Autodesk Fusion 360 part; units mm, degrees
(part 2 of 5)
sketch "草图4" plane through (0, 0, 25.97) normal (0, 0, 1) x (1, 0, 0) in component "01_月饼_金_68mm"
  line L0 (12.6, 0) -> (12.5848, 0.6183)
  line L1 (12.5848, 0.6183) -> (12.5393, 1.235)
  line L2 (12.5393, 1.235) -> (12.4636, 1.8488)
  line L3 (12.4636, 1.8488) -> (12.3579, 2.4581)
  line L4 (12.3579, 2.4581) -> (12.2224, 3.0616)
  line L5 (12.2224, 3.0616) -> (12.0574, 3.6576)
  line L6 (12.0574, 3.6576) -> (11.8635, 4.2448)
  line L7 (11.8635, 4.2448) -> (11.6409, 4.8218)
  line L8 (11.6409, 4.8218) -> (11.3903, 5.3872)
  line L9 (11.3903, 5.3872) -> (11.1122, 5.9396)
  line L10 (11.1122, 5.9396) -> (10.8074, 6.4777)
  line L11 (10.8074, 6.4777) -> (10.4765, 7.0002)
  line L12 (10.4765, 7.0002) -> (10.1204, 7.5058)
  line L13 (10.1204, 7.5058) -> (9.7399, 7.9934)
  line L14 (9.7399, 7.9934) -> (9.336, 8.4616)
  line L15 (9.336, 8.4616) -> (8.9095, 8.9095)
  line L16 (8.9095, 8.9095) -> (8.4616, 9.336)
  line L17 (8.4616, 9.336) -> (7.9934, 9.7399)
  line L18 (7.9934, 9.7399) -> (7.5058, 10.1204)
  line L19 (7.5058, 10.1204) -> (7.0002, 10.4765)
  line L20 (7.0002, 10.4765) -> (6.4777, 10.8074)
  line L21 (6.4777, 10.8074) -> (5.9396, 11.1122)
  line L22 (5.9396, 11.1122) -> (5.3872, 11.3903)
  line L23 (5.3872, 11.3903) -> (4.8218, 11.6409)
  line L24 (4.8218, 11.6409) -> (4.2448, 11.8635)
  line L25 (4.2448, 11.8635) -> (3.6576, 12.0574)
  line L26 (3.6576, 12.0574) -> (3.0616, 12.2224)
  line L27 (3.0616, 12.2224) -> (2.4581, 12.3579)
  line L28 (2.4581, 12.3579) -> (1.8488, 12.4636)
  line L29 (1.8488, 12.4636) -> (1.235, 12.5393)
  line L30 (1.235, 12.5393) -> (0.6183, 12.5848)
  line L31 (0.6183, 12.5848) -> (0, 12.6)
  line L32 (0, 12.6) -> (-0.6183, 12.5848)
  line L33 (-0.6183, 12.5848) -> (-1.235, 12.5393)
  line L34 (-1.235, 12.5393) -> (-1.8488, 12.4636)
  line L35 (-1.8488, 12.4636) -> (-2.4581, 12.3579)
  line L36 (-2.4581, 12.3579) -> (-3.0616, 12.2224)
  line L37 (-3.0616, 12.2224) -> (-3.6576, 12.0574)
  line L38 (-3.6576, 12.0574) -> (-4.2448, 11.8635)
  line L39 (-4.2448, 11.8635) -> (-4.8218, 11.6409)
  line L40 (-4.8218, 11.6409) -> (-5.3872, 11.3903)
  line L41 (-5.3872, 11.3903) -> (-5.9396, 11.1122)
  line L42 (-5.9396, 11.1122) -> (-6.4777, 10.8074)
  line L43 (-6.4777, 10.8074) -> (-7.0002, 10.4765)
  line L44 (-7.0002, 10.4765) -> (-7.5058, 10.1204)
  line L45 (-7.5058, 10.1204) -> (-7.9934, 9.7399)
  line L46 (-7.9934, 9.7399) -> (-8.4616, 9.336)
  line L47 (-8.4616, 9.336) -> (-8.9095, 8.9095)
  line L48 (-8.9095, 8.9095) -> (-9.336, 8.4616)
  line L49 (-9.336, 8.4616) -> (-9.7399, 7.9934)
  line L50 (-9.7399, 7.9934) -> (-10.1204, 7.5058)
  line L51 (-10.1204, 7.5058) -> (-10.4765, 7.0002)
  line L52 (-10.4765, 7.0002) -> (-10.8074, 6.4777)
  line L53 (-10.8074, 6.4777) -> (-11.1122, 5.9396)
  line L54 (-11.1122, 5.9396) -> (-11.3903, 5.3872)
  line L55 (-11.3903, 5.3872) -> (-11.6409, 4.8218)
  line L56 (-11.6409, 4.8218) -> (-11.8635, 4.2448)
  line L57 (-11.8635, 4.2448) -> (-12.0574, 3.6576)
  line L58 (-12.0574, 3.6576) -> (-12.2224, 3.0616)
  line L59 (-12.2224, 3.0616) -> (-12.3579, 2.4581)
  line L60 (-12.3579, 2.4581) -> (-12.4636, 1.8488)
  line L61 (-12.4636, 1.8488) -> (-12.5393, 1.235)
  line L62 (-12.5393, 1.235) -> (-12.5848, 0.6183)
  line L63 (-12.5848, 0.6183) -> (-12.6, 0)
  line L64 (-12.6, 0) -> (-12.5848, -0.6183)
  line L65 (-12.5848, -0.6183) -> (-12.5393, -1.235)
  line L66 (-12.5393, -1.235) -> (-12.4636, -1.8488)
  line L67 (-12.4636, -1.8488) -> (-12.3579, -2.4581)
  line L68 (-12.3579, -2.4581) -> (-12.2224, -3.0616)
  line L69 (-12.2224, -3.0616) -> (-12.0574, -3.6576)
  line L70 (-12.0574, -3.6576) -> (-11.8635, -4.2448)
  line L71 (-11.8635, -4.2448) -> (-11.6409, -4.8218)
  line L72 (-11.6409, -4.8218) -> (-11.3903, -5.3872)
  line L73 (-11.3903, -5.3872) -> (-11.1122, -5.9396)
  line L74 (-11.1122, -5.9396) -> (-10.8074, -6.4777)
  line L75 (-10.8074, -6.4777) -> (-10.4765, -7.0002)
  line L76 (-10.4765, -7.0002) -> (-10.1204, -7.5058)
  line L77 (-10.1204, -7.5058) -> (-9.7399, -7.9934)
  line L78 (-9.7399, -7.9934) -> (-9.336, -8.4616)
  line L79 (-9.336, -8.4616) -> (-8.9095, -8.9095)
  line L80 (-8.9095, -8.9095) -> (-8.4616, -9.336)
  line L81 (-8.4616, -9.336) -> (-7.9934, -9.7399)
  line L82 (-7.9934, -9.7399) -> (-7.5058, -10.1204)
  line L83 (-7.5058, -10.1204) -> (-7.0002, -10.4765)
  line L84 (-7.0002, -10.4765) -> (-6.4777, -10.8074)
  line L85 (-6.4777, -10.8074) -> (-5.9396, -11.1122)
  line L86 (-5.9396, -11.1122) -> (-5.3872, -11.3903)
  line L87 (-5.3872, -11.3903) -> (-4.8218, -11.6409)
  line L88 (-4.8218, -11.6409) -> (-4.2448, -11.8635)
  line L89 (-4.2448, -11.8635) -> (-3.6576, -12.0574)
  line L90 (-3.6576, -12.0574) -> (-3.0616, -12.2224)
  line L91 (-3.0616, -12.2224) -> (-2.4581, -12.3579)
  line L92 (-2.4581, -12.3579) -> (-1.8488, -12.4636)
  line L93 (-1.8488, -12.4636) -> (-1.235, -12.5393)
  line L94 (-1.235, -12.5393) -> (-0.6183, -12.5848)
  line L95 (-0.6183, -12.5848) -> (0, -12.6)
  line L96 (0, -12.6) -> (0.6183, -12.5848)
  line L97 (0.6183, -12.5848) -> (1.235, -12.5393)
  line L98 (1.235, -12.5393) -> (1.8488, -12.4636)
  line L99 (1.8488, -12.4636) -> (2.4581, -12.3579)
  line L100 (2.4581, -12.3579) -> (3.0616, -12.2224)
  line L101 (3.0616, -12.2224) -> (3.6576, -12.0574)
  line L102 (3.6576, -12.0574) -> (4.2448, -11.8635)
  line L103 (4.2448, -11.8635) -> (4.8218, -11.6409)
  line L104 (4.8218, -11.6409) -> (5.3872, -11.3903)
  line L105 (5.3872, -11.3903) -> (5.9396, -11.1122)
  line L106 (5.9396, -11.1122) -> (6.4777, -10.8074)
  line L107 (6.4777, -10.8074) -> (7.0002, -10.4765)
  line L108 (7.0002, -10.4765) -> (7.5058, -10.1204)
  line L109 (7.5058, -10.1204) -> (7.9934, -9.7399)
  line L110 (7.9934, -9.7399) -> (8.4616, -9.336)
  line L111 (8.4616, -9.336) -> (8.9095, -8.9095)
  line L112 (8.9095, -8.9095) -> (9.336, -8.4616)
  line L113 (9.336, -8.4616) -> (9.7399, -7.9934)
  line L114 (9.7399, -7.9934) -> (10.1204, -7.5058)
  line L115 (10.1204, -7.5058) -> (10.4765, -7.0002)
  line L116 (10.4765, -7.0002) -> (10.8074, -6.4777)
  line L117 (10.8074, -6.4777) -> (11.1122, -5.9396)
  line L118 (11.1122, -5.9396) -> (11.3903, -5.3872)
  line L119 (11.3903, -5.3872) -> (11.6409, -4.8218)
  line L120 (11.6409, -4.8218) -> (11.8635, -4.2448)
  line L121 (11.8635, -4.2448) -> (12.0574, -3.6576)
  line L122 (12.0574, -3.6576) -> (12.2224, -3.0616)
  line L123 (12.2224, -3.0616) -> (12.3579, -2.4581)
  line L124 (12.3579, -2.4581) -> (12.4636, -1.8488)
  line L125 (12.4636, -1.8488) -> (12.5393, -1.235)
  line L126 (12.5393, -1.235) -> (12.5848, -0.6183)
  line L127 (12.5848, -0.6183) -> (12.6, 0)
  line L128 (11.7858, -0.579) -> (11.7432, -1.1566)
  line L129 (11.7432, -1.1566) -> (11.6723, -1.7314)
  line L130 (11.6723, -1.7314) -> (11.5733, -2.3021)
  line L131 (11.5733, -2.3021) -> (11.4464, -2.8672)
  line L132 (11.4464, -2.8672) -> (11.2919, -3.4254)
  line L133 (11.2919, -3.4254) -> (11.1102, -3.9753)
  line L134 (11.1102, -3.9753) -> (10.9018, -4.5157)
  line L135 (10.9018, -4.5157) -> (10.6671, -5.0452)
  line L136 (10.6671, -5.0452) -> (10.4067, -5.5625)
  line L137 (10.4067, -5.5625) -> (10.1212, -6.0664)
  line L138 (10.1212, -6.0664) -> (9.8113, -6.5557)
  line L139 (9.8113, -6.5557) -> (9.4778, -7.0293)
  line L140 (9.4778, -7.0293) -> (9.1215, -7.4858)
  line L141 (9.1215, -7.4858) -> (8.7432, -7.9244)
  line L142 (8.7432, -7.9244) -> (8.3439, -8.3439)
  line L143 (8.3439, -8.3439) -> (7.9244, -8.7432)
  line L144 (7.9244, -8.7432) -> (7.4858, -9.1215)
  line L145 (7.4858, -9.1215) -> (7.0293, -9.4778)
  line L146 (7.0293, -9.4778) -> (6.5557, -9.8113)
  line L147 (6.5557, -9.8113) -> (6.0664, -10.1212)
  line L148 (6.0664, -10.1212) -> (5.5625, -10.4067)
  line L149 (5.5625, -10.4067) -> (5.0452, -10.6671)
  line L150 (5.0452, -10.6671) -> (4.5157, -10.9018)
  line L151 (4.5157, -10.9018) -> (3.9753, -11.1102)
  line L152 (3.9753, -11.1102) -> (3.4254, -11.2919)
  line L153 (3.4254, -11.2919) -> (2.8672, -11.4464)
  line L154 (2.8672, -11.4464) -> (2.3021, -11.5733)
  line L155 (2.3021, -11.5733) -> (1.7314, -11.6723)
  line L156 (1.7314, -11.6723) -> (1.1566, -11.7432)
  line L157 (1.1566, -11.7432) -> (0.579, -11.7858)
  line L158 (0.579, -11.7858) -> (0, -11.8)
  line L159 (0, -11.8) -> (-0.579, -11.7858)
  line L160 (-0.579, -11.7858) -> (-1.1566, -11.7432)
  line L161 (-1.1566, -11.7432) -> (-1.7314, -11.6723)
  line L162 (-1.7314, -11.6723) -> (-2.3021, -11.5733)
  line L163 (-2.3021, -11.5733) -> (-2.8672, -11.4464)
  line L164 (-2.8672, -11.4464) -> (-3.4254, -11.2919)
  line L165 (-3.4254, -11.2919) -> (-3.9753, -11.1102)
  line L166 (-3.9753, -11.1102) -> (-4.5157, -10.9018)
  line L167 (-4.5157, -10.9018) -> (-5.0452, -10.6671)
  line L168 (-5.0452, -10.6671) -> (-5.5625, -10.4067)
  line L169 (-5.5625, -10.4067) -> (-6.0664, -10.1212)
  line L170 (-6.0664, -10.1212) -> (-6.5557, -9.8113)
  line L171 (-6.5557, -9.8113) -> (-7.0293, -9.4778)
  line L172 (-7.0293, -9.4778) -> (-7.4858, -9.1215)
  line L173 (-7.4858, -9.1215) -> (-7.9244, -8.7432)
  line L174 (-7.9244, -8.7432) -> (-8.3439, -8.3439)
  line L175 (-8.3439, -8.3439) -> (-8.7432, -7.9244)
  line L176 (-8.7432, -7.9244) -> (-9.1215, -7.4858)
  line L177 (-9.1215, -7.4858) -> (-9.4778, -7.0293)
  line L178 (-9.4778, -7.0293) -> (-9.8113, -6.5557)
  line L179 (-9.8113, -6.5557) -> (-10.1212, -6.0664)
  line L180 (-10.1212, -6.0664) -> (-10.4067, -5.5625)
  line L181 (-10.4067, -5.5625) -> (-10.6671, -5.0452)
  line L182 (-10.6671, -5.0452) -> (-10.9018, -4.5157)
  line L183 (-10.9018, -4.5157) -> (-11.1102, -3.9753)
  line L184 (-11.1102, -3.9753) -> (-11.2919, -3.4254)
  line L185 (-11.2919, -3.4254) -> (-11.4464, -2.8672)
  line L186 (-11.4464, -2.8672) -> (-11.5733, -2.3021)
  line L187 (-11.5733, -2.3021) -> (-11.6723, -1.7314)
  line L188 (-11.6723, -1.7314) -> (-11.7432, -1.1566)
  line L189 (-11.7432, -1.1566) -> (-11.7858, -0.579)
  line L190 (-11.7858, -0.579) -> (-11.8, 0)
  line L191 (-11.8, 0) -> (-11.7858, 0.579)
  line L192 (-11.7858, 0.579) -> (-11.7432, 1.1566)
  line L193 (-11.7432, 1.1566) -> (-11.6723, 1.7314)
  line L194 (-11.6723, 1.7314) -> (-11.5733, 2.3021)
  line L195 (-11.5733, 2.3021) -> (-11.4464, 2.8672)
  line L196 (-11.4464, 2.8672) -> (-11.2919, 3.4254)
  line L197 (-11.2919, 3.4254) -> (-11.1102, 3.9753)
  line L198 (-11.1102, 3.9753) -> (-10.9018, 4.5157)
  line L199 (-10.9018, 4.5157) -> (-10.6671, 5.0452)
  line L200 (-10.6671, 5.0452) -> (-10.4067, 5.5625)
  line L201 (-10.4067, 5.5625) -> (-10.1212, 6.0664)
  line L202 (-10.1212, 6.0664) -> (-9.8113, 6.5557)
  line L203 (-9.8113, 6.5557) -> (-9.4778, 7.0293)
  line L204 (-9.4778, 7.0293) -> (-9.1215, 7.4858)
  line L205 (-9.1215, 7.4858) -> (-8.7432, 7.9244)
  line L206 (-8.7432, 7.9244) -> (-8.3439, 8.3439)
  line L207 (-8.3439, 8.3439) -> (-7.9244, 8.7432)
  line L208 (-7.9244, 8.7432) -> (-7.4858, 9.1215)
  line L209 (-7.4858, 9.1215) -> (-7.0293, 9.4778)
  line L210 (-7.0293, 9.4778) -> (-6.5557, 9.8113)
  line L211 (-6.5557, 9.8113) -> (-6.0664, 10.1212)
  line L212 (-6.0664, 10.1212) -> (-5.5625, 10.4067)
  line L213 (-5.5625, 10.4067) -> (-5.0452, 10.6671)
  line L214 (-5.0452, 10.6671) -> (-4.5157, 10.9018)
  line L215 (-4.5157, 10.9018) -> (-3.9753, 11.1102)
  line L216 (-3.9753, 11.1102) -> (-3.4254, 11.2919)
  line L217 (-3.4254, 11.2919) -> (-2.8672, 11.4464)
  line L218 (-2.8672, 11.4464) -> (-2.3021, 11.5733)
  line L219 (-2.3021, 11.5733) -> (-1.7314, 11.6723)
  line L220 (-1.7314, 11.6723) -> (-1.1566, 11.7432)
  line L221 (-1.1566, 11.7432) -> (-0.579, 11.7858)
  line L222 (-0.579, 11.7858) -> (0, 11.8)
  line L223 (0, 11.8) -> (0.579, 11.7858)
  line L224 (0.579, 11.7858) -> (1.1566, 11.7432)
  line L225 (1.1566, 11.7432) -> (1.7314, 11.6723)
  line L226 (1.7314, 11.6723) -> (2.3021, 11.5733)
  line L227 (2.3021, 11.5733) -> (2.8672, 11.4464)
  line L228 (2.8672, 11.4464) -> (3.4254, 11.2919)
  line L229 (3.4254, 11.2919) -> (3.9753, 11.1102)
  line L230 (3.9753, 11.1102) -> (4.5157, 10.9018)
  line L231 (4.5157, 10.9018) -> (5.0452, 10.6671)
  line L232 (5.0452, 10.6671) -> (5.5625, 10.4067)
  line L233 (5.5625, 10.4067) -> (6.0664, 10.1212)
  line L234 (6.0664, 10.1212) -> (6.5557, 9.8113)
  line L235 (6.5557, 9.8113) -> (7.0293, 9.4778)
  line L236 (7.0293, 9.4778) -> (7.4858, 9.1215)
  line L237 (7.4858, 9.1215) -> (7.9244, 8.7432)
  line L238 (7.9244, 8.7432) -> (8.3439, 8.3439)
  line L239 (8.3439, 8.3439) -> (8.7432, 7.9244)
  line L240 (8.7432, 7.9244) -> (9.1215, 7.4858)
  line L241 (9.1215, 7.4858) -> (9.4778, 7.0293)
  line L242 (9.4778, 7.0293) -> (9.8113, 6.5557)
  line L243 (9.8113, 6.5557) -> (10.1212, 6.0664)
  line L244 (10.1212, 6.0664) -> (10.4067, 5.5625)
  line L245 (10.4067, 5.5625) -> (10.6671, 5.0452)
  line L246 (10.6671, 5.0452) -> (10.9018, 4.5157)
  line L247 (10.9018, 4.5157) -> (11.1102, 3.9753)
  line L248 (11.1102, 3.9753) -> (11.2919, 3.4254)
  line L249 (11.2919, 3.4254) -> (11.4464, 2.8672)
  line L250 (11.4464, 2.8672) -> (11.5733, 2.3021)
  line L251 (11.5733, 2.3021) -> (11.6723, 1.7314)
  line L252 (11.6723, 1.7314) -> (11.7432, 1.1566)
  line L253 (11.7432, 1.1566) -> (11.7858, 0.579)
  line L254 (11.7858, 0.579) -> (11.8, 0)
  line L255 (11.8, 0) -> (11.7858, -0.579)
extrude "团圆内环_003 (1)" add sketch "草图4" along normal blind 1.63 bodies 1 in component "01_月饼_金_68mm"
sketch "草图5" plane through (0, 0, 25.97) normal (0, 0, 1) x (1, 0, 0) in component "01_月饼_金_68mm"
  line L0 (23.66, 0) -> (23.5783, 0.5788)
  line L1 (23.5783, 0.5788) -> (23.3448, 1.1469)
  line L2 (23.3448, 1.1469) -> (22.9926, 1.696)
  line L3 (22.9926, 1.696) -> (22.5708, 2.223)
  line L4 (22.5708, 2.223) -> (22.1372, 2.7304)
  line L5 (22.1372, 2.7304) -> (21.7491, 3.2262)
  line L6 (21.7491, 3.2262) -> (21.454, 3.7226)
  line L7 (21.454, 3.7226) -> (21.283, 4.2335)
  line L8 (21.283, 4.2335) -> (21.2455, 4.7708)
  line L9 (21.2455, 4.7708) -> (21.3281, 5.3424)
  line L10 (21.3281, 5.3424) -> (21.497, 5.949)
  line L11 (21.497, 5.949) -> (21.7034, 6.5837)
  line L12 (21.7034, 6.5837) -> (21.8914, 7.2319)
  line L13 (21.8914, 7.2319) -> (22.0067, 7.8741)
  line L14 (22.0067, 7.8741) -> (22.005, 8.4883)
  line L15 (22.005, 8.4883) -> (21.859, 9.0543)
  line L16 (21.859, 9.0543) -> (21.562, 9.5578)
  line L17 (21.562, 9.5578) -> (21.1289, 9.9932)
  line L18 (21.1289, 9.9932) -> (20.5933, 10.3658)
  line L19 (20.5933, 10.3658) -> (20.002, 10.6913)
  line L20 (20.002, 10.6913) -> (19.4073, 10.9941)
  line L21 (19.4073, 10.9941) -> (18.8589, 11.3036)
  line L22 (18.8589, 11.3036) -> (18.3963, 11.6494)
  line L23 (18.3963, 11.6494) -> (18.0429, 12.0559)
  line L24 (18.0429, 12.0559) -> (17.8026, 12.538)
  line L25 (17.8026, 12.538) -> (17.6602, 13.0977)
  line L26 (17.6602, 13.0977) -> (17.584, 13.7227)
  line L27 (17.584, 13.7227) -> (17.5319, 14.388)
  line L28 (17.5319, 14.388) -> (17.4575, 15.0589)
  line L29 (17.4575, 15.0589) -> (17.3182, 15.6963)
  line L30 (17.3182, 15.6963) -> (17.0817, 16.2631)
  line L31 (17.0817, 16.2631) -> (16.7301, 16.7301)
  line L32 (16.7301, 16.7301) -> (16.2631, 17.0817)
  line L33 (16.2631, 17.0817) -> (15.6963, 17.3182)
  line L34 (15.6963, 17.3182) -> (15.0589, 17.4575)
  line L35 (15.0589, 17.4575) -> (14.388, 17.5319)
  line L36 (14.388, 17.5319) -> (13.7227, 17.584)
  line L37 (13.7227, 17.584) -> (13.0977, 17.6602)
  line L38 (13.0977, 17.6602) -> (12.538, 17.8026)
  line L39 (12.538, 17.8026) -> (12.0559, 18.0429)
  line L40 (12.0559, 18.0429) -> (11.6494, 18.3963)
  line L41 (11.6494, 18.3963) -> (11.3036, 18.8589)
  line L42 (11.3036, 18.8589) -> (10.9941, 19.4073)
  line L43 (10.9941, 19.4073) -> (10.6913, 20.002)
  line L44 (10.6913, 20.002) -> (10.3658, 20.5933)
  line L45 (10.3658, 20.5933) -> (9.9932, 21.1289)
  line L46 (9.9932, 21.1289) -> (9.5578, 21.562)
  line L47 (9.5578, 21.562) -> (9.0543, 21.859)
  line L48 (9.0543, 21.859) -> (8.4883, 22.005)
  line L49 (8.4883, 22.005) -> (7.8741, 22.0067)
  line L50 (7.8741, 22.0067) -> (7.2319, 21.8914)
  line L51 (7.2319, 21.8914) -> (6.5837, 21.7034)
  line L52 (6.5837, 21.7034) -> (5.949, 21.497)
  line L53 (5.949, 21.497) -> (5.3424, 21.3281)
  line L54 (5.3424, 21.3281) -> (4.7708, 21.2455)
  line L55 (4.7708, 21.2455) -> (4.2335, 21.283)
  line L56 (4.2335, 21.283) -> (3.7226, 21.454)
  line L57 (3.7226, 21.454) -> (3.2262, 21.7491)
  line L58 (3.2262, 21.7491) -> (2.7304, 22.1372)
  line L59 (2.7304, 22.1372) -> (2.223, 22.5708)
  line L60 (2.223, 22.5708) -> (1.696, 22.9926)
  line L61 (1.696, 22.9926) -> (1.1469, 23.3448)
  line L62 (1.1469, 23.3448) -> (0.5788, 23.5783)
  line L63 (0.5788, 23.5783) -> (0, 23.66)
  line L64 (0, 23.66) -> (-0.5788, 23.5783)
  line L65 (-0.5788, 23.5783) -> (-1.1469, 23.3448)
  line L66 (-1.1469, 23.3448) -> (-1.696, 22.9926)
  line L67 (-1.696, 22.9926) -> (-2.223, 22.5708)
  line L68 (-2.223, 22.5708) -> (-2.7304, 22.1372)
  line L69 (-2.7304, 22.1372) -> (-3.2262, 21.7491)
  line L70 (-3.2262, 21.7491) -> (-3.7226, 21.454)
  line L71 (-3.7226, 21.454) -> (-4.2335, 21.283)
  line L72 (-4.2335, 21.283) -> (-4.7708, 21.2455)
  line L73 (-4.7708, 21.2455) -> (-5.3424, 21.3281)
  line L74 (-5.3424, 21.3281) -> (-5.949, 21.497)
  line L75 (-5.949, 21.497) -> (-6.5837, 21.7034)
  line L76 (-6.5837, 21.7034) -> (-7.2319, 21.8914)
  line L77 (-7.2319, 21.8914) -> (-7.8741, 22.0067)
  line L78 (-7.8741, 22.0067) -> (-8.4883, 22.005)
  line L79 (-8.4883, 22.005) -> (-9.0543, 21.859)
  line L80 (-9.0543, 21.859) -> (-9.5578, 21.562)
  line L81 (-9.5578, 21.562) -> (-9.9932, 21.1289)
  line L82 (-9.9932, 21.1289) -> (-10.3658, 20.5933)
  line L83 (-10.3658, 20.5933) -> (-10.6913, 20.002)
  line L84 (-10.6913, 20.002) -> (-10.9941, 19.4073)
  line L85 (-10.9941, 19.4073) -> (-11.3036, 18.8589)
  line L86 (-11.3036, 18.8589) -> (-11.6494, 18.3963)
  line L87 (-11.6494, 18.3963) -> (-12.0559, 18.0429)
  line L88 (-12.0559, 18.0429) -> (-12.538, 17.8026)
  line L89 (-12.538, 17.8026) -> (-13.0977, 17.6602)
  line L90 (-13.0977, 17.6602) -> (-13.7227, 17.584)
  line L91 (-13.7227, 17.584) -> (-14.388, 17.5319)
  line L92 (-14.388, 17.5319) -> (-15.0589, 17.4575)
  line L93 (-15.0589, 17.4575) -> (-15.6963, 17.3182)
  line L94 (-15.6963, 17.3182) -> (-16.2631, 17.0817)
  line L95 (-16.2631, 17.0817) -> (-16.7301, 16.7301)
  line L96 (-16.7301, 16.7301) -> (-17.0817, 16.2631)
  line L97 (-17.0817, 16.2631) -> (-17.3182, 15.6963)
  line L98 (-17.3182, 15.6963) -> (-17.4575, 15.0589)
  line L99 (-17.4575, 15.0589) -> (-17.5319, 14.388)
  line L100 (-17.5319, 14.388) -> (-17.584, 13.7227)
  line L101 (-17.584, 13.7227) -> (-17.6602, 13.0977)
  line L102 (-17.6602, 13.0977) -> (-17.8026, 12.538)
  line L103 (-17.8026, 12.538) -> (-18.0429, 12.0559)
  line L104 (-18.0429, 12.0559) -> (-18.3963, 11.6494)
  line L105 (-18.3963, 11.6494) -> (-18.8589, 11.3036)
  line L106 (-18.8589, 11.3036) -> (-19.4073, 10.9941)
  line L107 (-19.4073, 10.9941) -> (-20.002, 10.6913)
  line L108 (-20.002, 10.6913) -> (-20.5933, 10.3658)
  line L109 (-20.5933, 10.3658) -> (-21.1289, 9.9932)
  line L110 (-21.1289, 9.9932) -> (-21.562, 9.5578)
  line L111 (-21.562, 9.5578) -> (-21.859, 9.0543)
  line L112 (-21.859, 9.0543) -> (-22.005, 8.4883)
  line L113 (-22.005, 8.4883) -> (-22.0067, 7.8741)
  line L114 (-22.0067, 7.8741) -> (-21.8914, 7.2319)
  line L115 (-21.8914, 7.2319) -> (-21.7034, 6.5837)
  line L116 (-21.7034, 6.5837) -> (-21.497, 5.949)
  line L117 (-21.497, 5.949) -> (-21.3281, 5.3424)
  line L118 (-21.3281, 5.3424) -> (-21.2455, 4.7708)
  line L119 (-21.2455, 4.7708) -> (-21.283, 4.2335)
  line L120 (-21.283, 4.2335) -> (-21.454, 3.7226)
  line L121 (-21.454, 3.7226) -> (-21.7491, 3.2262)
  line L122 (-21.7491, 3.2262) -> (-22.1372, 2.7304)
  line L123 (-22.1372, 2.7304) -> (-22.5708, 2.223)
  line L124 (-22.5708, 2.223) -> (-22.9926, 1.696)
  line L125 (-22.9926, 1.696) -> (-23.3448, 1.1469)
  line L126 (-23.3448, 1.1469) -> (-23.5783, 0.5788)
  line L127 (-23.5783, 0.5788) -> (-23.66, 0)
  line L128 (-23.66, 0) -> (-23.5783, -0.5788)
  line L129 (-23.5783, -0.5788) -> (-23.3448, -1.1469)
  line L130 (-23.3448, -1.1469) -> (-22.9926, -1.696)
  line L131 (-22.9926, -1.696) -> (-22.5708, -2.223)
  line L132 (-22.5708, -2.223) -> (-22.1372, -2.7304)
  line L133 (-22.1372, -2.7304) -> (-21.7491, -3.2262)
  line L134 (-21.7491, -3.2262) -> (-21.454, -3.7226)
  line L135 (-21.454, -3.7226) -> (-21.283, -4.2335)
  line L136 (-21.283, -4.2335) -> (-21.2455, -4.7708)
  line L137 (-21.2455, -4.7708) -> (-21.3281, -5.3424)
  line L138 (-21.3281, -5.3424) -> (-21.497, -5.949)
  line L139 (-21.497, -5.949) -> (-21.7034, -6.5837)
  line L140 (-21.7034, -6.5837) -> (-21.8914, -7.2319)
  line L141 (-21.8914, -7.2319) -> (-22.0067, -7.8741)
  line L142 (-22.0067, -7.8741) -> (-22.005, -8.4883)
  line L143 (-22.005, -8.4883) -> (-21.859, -9.0543)
  line L144 (-21.859, -9.0543) -> (-21.562, -9.5578)
  line L145 (-21.562, -9.5578) -> (-21.1289, -9.9932)
  line L146 (-21.1289, -9.9932) -> (-20.5933, -10.3658)
  line L147 (-20.5933, -10.3658) -> (-20.002, -10.6913)
  line L148 (-20.002, -10.6913) -> (-19.4073, -10.9941)
  line L149 (-19.4073, -10.9941) -> (-18.8589, -11.3036)
  line L150 (-18.8589, -11.3036) -> (-18.3963, -11.6494)
  line L151 (-18.3963, -11.6494) -> (-18.0429, -12.0559)
  line L152 (-18.0429, -12.0559) -> (-17.8026, -12.538)
  line L153 (-17.8026, -12.538) -> (-17.6602, -13.0977)
  line L154 (-17.6602, -13.0977) -> (-17.584, -13.7227)
  line L155 (-17.584, -13.7227) -> (-17.5319, -14.388)
  line L156 (-17.5319, -14.388) -> (-17.4575, -15.0589)
  line L157 (-17.4575, -15.0589) -> (-17.3182, -15.6963)
  line L158 (-17.3182, -15.6963) -> (-17.0817, -16.2631)
  line L159 (-17.0817, -16.2631) -> (-16.7301, -16.7301)
  line L160 (-16.7301, -16.7301) -> (-16.2631, -17.0817)
  line L161 (-16.2631, -17.0817) -> (-15.6963, -17.3182)
  line L162 (-15.6963, -17.3182) -> (-15.0589, -17.4575)
  line L163 (-15.0589, -17.4575) -> (-14.388, -17.5319)
  line L164 (-14.388, -17.5319) -> (-13.7227, -17.584)
  line L165 (-13.7227, -17.584) -> (-13.0977, -17.6602)
  line L166 (-13.0977, -17.6602) -> (-12.538, -17.8026)
  line L167 (-12.538, -17.8026) -> (-12.0559, -18.0429)
  line L168 (-12.0559, -18.0429) -> (-11.6494, -18.3963)
  line L169 (-11.6494, -18.3963) -> (-11.3036, -18.8589)
  line L170 (-11.3036, -18.8589) -> (-10.9941, -19.4073)
  line L171 (-10.9941, -19.4073) -> (-10.6913, -20.002)
  line L172 (-10.6913, -20.002) -> (-10.3658, -20.5933)
  line L173 (-10.3658, -20.5933) -> (-9.9932, -21.1289)
  line L174 (-9.9932, -21.1289) -> (-9.5578, -21.562)
  line L175 (-9.5578, -21.562) -> (-9.0543, -21.859)
  line L176 (-9.0543, -21.859) -> (-8.4883, -22.005)
  line L177 (-8.4883, -22.005) -> (-7.8741, -22.0067)
  line L178 (-7.8741, -22.0067) -> (-7.2319, -21.8914)
  line L179 (-7.2319, -21.8914) -> (-6.5837, -21.7034)
  line L180 (-6.5837, -21.7034) -> (-5.949, -21.497)
  line L181 (-5.949, -21.497) -> (-5.3424, -21.3281)
  line L182 (-5.3424, -21.3281) -> (-4.7708, -21.2455)
  line L183 (-4.7708, -21.2455) -> (-4.2335, -21.283)
  line L184 (-4.2335, -21.283) -> (-3.7226, -21.454)
  line L185 (-3.7226, -21.454) -> (-3.2262, -21.7491)
  line L186 (-3.2262, -21.7491) -> (-2.7304, -22.1372)
  line L187 (-2.7304, -22.1372) -> (-2.223, -22.5708)
  line L188 (-2.223, -22.5708) -> (-1.696, -22.9926)
  line L189 (-1.696, -22.9926) -> (-1.1469, -23.3448)
  line L190 (-1.1469, -23.3448) -> (-0.5788, -23.5783)
  line L191 (-0.5788, -23.5783) -> (0, -23.66)
  line L192 (0, -23.66) -> (0.5788, -23.5783)
  line L193 (0.5788, -23.5783) -> (1.1469, -23.3448)
  line L194 (1.1469, -23.3448) -> (1.696, -22.9926)
  line L195 (1.696, -22.9926) -> (2.223, -22.5708)
  line L196 (2.223, -22.5708) -> (2.7304, -22.1372)
  line L197 (2.7304, -22.1372) -> (3.2262, -21.7491)
  line L198 (3.2262, -21.7491) -> (3.7226, -21.454)
  line L199 (3.7226, -21.454) -> (4.2335, -21.283)
  line L200 (4.2335, -21.283) -> (4.7708, -21.2455)
  line L201 (4.7708, -21.2455) -> (5.3424, -21.3281)
  line L202 (5.3424, -21.3281) -> (5.949, -21.497)
  line L203 (5.949, -21.497) -> (6.5837, -21.7034)
  line L204 (6.5837, -21.7034) -> (7.2319, -21.8914)
  line L205 (7.2319, -21.8914) -> (7.8741, -22.0067)
  line L206 (7.8741, -22.0067) -> (8.4883, -22.005)
  line L207 (8.4883, -22.005) -> (9.0543, -21.859)
  line L208 (9.0543, -21.859) -> (9.5578, -21.562)
  line L209 (9.5578, -21.562) -> (9.9932, -21.1289)
  line L210 (9.9932, -21.1289) -> (10.3658, -20.5933)
  line L211 (10.3658, -20.5933) -> (10.6913, -20.002)
  line L212 (10.6913, -20.002) -> (10.9941, -19.4073)
  line L213 (10.9941, -19.4073) -> (11.3036, -18.8589)
  line L214 (11.3036, -18.8589) -> (11.6494, -18.3963)
  line L215 (11.6494, -18.3963) -> (12.0559, -18.0429)
  line L216 (12.0559, -18.0429) -> (12.538, -17.8026)
  line L217 (12.538, -17.8026) -> (13.0977, -17.6602)
  line L218 (13.0977, -17.6602) -> (13.7227, -17.584)
  line L219 (13.7227, -17.584) -> (14.388, -17.5319)
  line L220 (14.388, -17.5319) -> (15.0589, -17.4575)
  line L221 (15.0589, -17.4575) -> (15.6963, -17.3182)
  line L222 (15.6963, -17.3182) -> (16.2631, -17.0817)
  line L223 (16.2631, -17.0817) -> (16.7301, -16.7301)
  line L224 (16.7301, -16.7301) -> (17.0817, -16.2631)
  line L225 (17.0817, -16.2631) -> (17.3182, -15.6963)
  line L226 (17.3182, -15.6963) -> (17.4575, -15.0589)
  line L227 (17.4575, -15.0589) -> (17.5319, -14.388)
  line L228 (17.5319, -14.388) -> (17.584, -13.7227)
  line L229 (17.584, -13.7227) -> (17.6602, -13.0977)
  line L230 (17.6602, -13.0977) -> (17.8026, -12.538)
  line L231 (17.8026, -12.538) -> (18.0429, -12.0559)
  line L232 (18.0429, -12.0559) -> (18.3963, -11.6494)
  line L233 (18.3963, -11.6494) -> (18.8589, -11.3036)
  line L234 (18.8589, -11.3036) -> (19.4073, -10.9941)
  line L235 (19.4073, -10.9941) -> (20.002, -10.6913)
  line L236 (20.002, -10.6913) -> (20.5933, -10.3658)
  line L237 (20.5933, -10.3658) -> (21.1289, -9.9932)
  line L238 (21.1289, -9.9932) -> (21.562, -9.5578)
  line L239 (21.562, -9.5578) -> (21.859, -9.0543)
  line L240 (21.859, -9.0543) -> (22.005, -8.4883)
  line L241 (22.005, -8.4883) -> (22.0067, -7.8741)
  line L242 (22.0067, -7.8741) -> (21.8914, -7.2319)
  line L243 (21.8914, -7.2319) -> (21.7034, -6.5837)
  line L244 (21.7034, -6.5837) -> (21.497, -5.949)
  line L245 (21.497, -5.949) -> (21.3281, -5.3424)
  line L246 (21.3281, -5.3424) -> (21.2455, -4.7708)
  line L247 (21.2455, -4.7708) -> (21.283, -4.2335)
  line L248 (21.283, -4.2335) -> (21.454, -3.7226)
  line L249 (21.454, -3.7226) -> (21.7491, -3.2262)
  line L250 (21.7491, -3.2262) -> (22.1372, -2.7304)
  line L251 (22.1372, -2.7304) -> (22.5708, -2.223)
  line L252 (22.5708, -2.223) -> (22.9926, -1.696)
  line L253 (22.9926, -1.696) -> (23.3448, -1.1469)
  line L254 (23.3448, -1.1469) -> (23.5783, -0.5788)
  line L255 (23.5783, -0.5788) -> (23.66, 0)
  line L256 (22.86, 0) -> (22.7785, -0.5592)
  line L257 (22.7785, -0.5592) -> (22.5458, -1.1076)
  line L258 (22.5458, -1.1076) -> (22.1947, -1.6372)
  line L259 (22.1947, -1.6372) -> (21.7746, -2.1446)
  line L260 (21.7746, -2.1446) -> (21.3432, -2.6324)
  line L261 (21.3432, -2.6324) -> (20.9577, -3.1088)
  line L262 (20.9577, -3.1088) -> (20.6658, -3.5859)
  line L263 (20.6658, -3.5859) -> (20.4984, -4.0774)
  line L264 (20.4984, -4.0774) -> (20.465, -4.5956)
  line L265 (20.465, -4.5956) -> (20.5521, -5.148)
  line L266 (20.5521, -5.148) -> (20.726, -5.7356)
  line L267 (20.726, -5.7356) -> (20.9379, -6.3514)
  line L268 (20.9379, -6.3514) -> (21.1318, -6.981)
  line L269 (21.1318, -6.981) -> (21.2534, -7.6046)
  line L270 (21.2534, -7.6046) -> (21.2586, -8.2004)
  line L271 (21.2586, -8.2004) -> (21.1199, -8.7481)
  line L272 (21.1199, -8.7481) -> (20.8306, -9.2336)
  line L273 (20.8306, -9.2336) -> (20.4057, -9.6512)
  line L274 (20.4057, -9.6512) -> (19.8787, -10.0061)
  line L275 (19.8787, -10.0061) -> (19.2964, -10.3142)
  line L276 (19.2964, -10.3142) -> (18.7112, -10.5998)
  line L277 (18.7112, -10.5998) -> (18.1727, -10.8923)
  line L278 (18.1727, -10.8923) -> (17.7205, -11.2214)
  line L279 (17.7205, -11.2214) -> (17.3777, -11.6114)
  line L280 (17.3777, -11.6114) -> (17.1485, -12.0773)
  line L281 (17.1485, -12.0773) -> (17.0176, -12.6211)
  line L282 (17.0176, -12.6211) -> (16.9534, -13.2305)
  line L283 (16.9534, -13.2305) -> (16.9135, -13.8805)
  line L284 (16.9135, -13.8805) -> (16.8517, -14.5364)
  line L285 (16.8517, -14.5364) -> (16.7255, -15.1591)
  line L286 (16.7255, -15.1591) -> (16.5023, -15.7115)
  line L287 (16.5023, -15.7115) -> (16.1645, -16.1645)
  line L288 (16.1645, -16.1645) -> (15.7115, -16.5023)
  line L289 (15.7115, -16.5023) -> (15.1591, -16.7255)
  line L290 (15.1591, -16.7255) -> (14.5364, -16.8517)
  line L291 (14.5364, -16.8517) -> (13.8805, -16.9135)
  line L292 (13.8805, -16.9135) -> (13.2305, -16.9534)
  line L293 (13.2305, -16.9534) -> (12.6211, -17.0176)
  line L294 (12.6211, -17.0176) -> (12.0773, -17.1485)
  line L295 (12.0773, -17.1485) -> (11.6114, -17.3777)
  line L296 (11.6114, -17.3777) -> (11.2214, -17.7205)
  line L297 (11.2214, -17.7205) -> (10.8923, -18.1727)
  line L298 (10.8923, -18.1727) -> (10.5998, -18.7112)
  line L299 (10.5998, -18.7112) -> (10.3142, -19.2964)
  line L300 (10.3142, -19.2964) -> (10.0061, -19.8787)
  line L301 (10.0061, -19.8787) -> (9.6512, -20.4057)
  line L302 (9.6512, -20.4057) -> (9.2336, -20.8306)
  line L303 (9.2336, -20.8306) -> (8.7481, -21.1199)
  line L304 (8.7481, -21.1199) -> (8.2004, -21.2586)
  line L305 (8.2004, -21.2586) -> (7.6046, -21.2534)
  line L306 (7.6046, -21.2534) -> (6.981, -21.1318)
  line L307 (6.981, -21.1318) -> (6.3514, -20.9379)
  line L308 (6.3514, -20.9379) -> (5.7356, -20.726)
  line L309 (5.7356, -20.726) -> (5.148, -20.5521)
  line L310 (5.148, -20.5521) -> (4.5956, -20.465)
  line L311 (4.5956, -20.465) -> (4.0774, -20.4984)
  line L312 (4.0774, -20.4984) -> (3.5859, -20.6658)
  line L313 (3.5859, -20.6658) -> (3.1088, -20.9577)
  line L314 (3.1088, -20.9577) -> (2.6324, -21.3432)
  line L315 (2.6324, -21.3432) -> (2.1446, -21.7746)
  line L316 (2.1446, -21.7746) -> (1.6372, -22.1947)
  line L317 (1.6372, -22.1947) -> (1.1076, -22.5458)
  line L318 (1.1076, -22.5458) -> (0.5592, -22.7785)
  line L319 (0.5592, -22.7785) -> (0, -22.86)
  line L320 (0, -22.86) -> (-0.5592, -22.7785)
  line L321 (-0.5592, -22.7785) -> (-1.1076, -22.5458)
  line L322 (-1.1076, -22.5458) -> (-1.6372, -22.1947)
  line L323 (-1.6372, -22.1947) -> (-2.1446, -21.7746)
  line L324 (-2.1446, -21.7746) -> (-2.6324, -21.3432)
  line L325 (-2.6324, -21.3432) -> (-3.1088, -20.9577)
  line L326 (-3.1088, -20.9577) -> (-3.5859, -20.6658)
  line L327 (-3.5859, -20.6658) -> (-4.0774, -20.4984)
  line L328 (-4.0774, -20.4984) -> (-4.5956, -20.465)
  line L329 (-4.5956, -20.465) -> (-5.148, -20.5521)
  line L330 (-5.148, -20.5521) -> (-5.7356, -20.726)
  line L331 (-5.7356, -20.726) -> (-6.3514, -20.9379)
  line L332 (-6.3514, -20.9379) -> (-6.981, -21.1318)
  line L333 (-6.981, -21.1318) -> (-7.6046, -21.2534)
  line L334 (-7.6046, -21.2534) -> (-8.2004, -21.2586)
  line L335 (-8.2004, -21.2586) -> (-8.7481, -21.1199)
  line L336 (-8.7481, -21.1199) -> (-9.2336, -20.8306)
  line L337 (-9.2336, -20.8306) -> (-9.6512, -20.4057)
  line L338 (-9.6512, -20.4057) -> (-10.0061, -19.8787)
  line L339 (-10.0061, -19.8787) -> (-10.3142, -19.2964)
  line L340 (-10.3142, -19.2964) -> (-10.5998, -18.7112)
  line L341 (-10.5998, -18.7112) -> (-10.8923, -18.1727)
  line L342 (-10.8923, -18.1727) -> (-11.2214, -17.7205)
  line L343 (-11.2214, -17.7205) -> (-11.6114, -17.3777)
  line L344 (-11.6114, -17.3777) -> (-12.0773, -17.1485)
  line L345 (-12.0773, -17.1485) -> (-12.6211, -17.0176)
  line L346 (-12.6211, -17.0176) -> (-13.2305, -16.9534)
  line L347 (-13.2305, -16.9534) -> (-13.8805, -16.9135)
  line L348 (-13.8805, -16.9135) -> (-14.5364, -16.8517)
  line L349 (-14.5364, -16.8517) -> (-15.1591, -16.7255)
  line L350 (-15.1591, -16.7255) -> (-15.7115, -16.5023)
  line L351 (-15.7115, -16.5023) -> (-16.1645, -16.1645)
  line L352 (-16.1645, -16.1645) -> (-16.5023, -15.7115)
  line L353 (-16.5023, -15.7115) -> (-16.7255, -15.1591)
  line L354 (-16.7255, -15.1591) -> (-16.8517, -14.5364)
  line L355 (-16.8517, -14.5364) -> (-16.9135, -13.8805)
  line L356 (-16.9135, -13.8805) -> (-16.9534, -13.2305)
  line L357 (-16.9534, -13.2305) -> (-17.0176, -12.6211)
  line L358 (-17.0176, -12.6211) -> (-17.1485, -12.0773)
  line L359 (-17.1485, -12.0773) -> (-17.3777, -11.6114)
  line L360 (-17.3777, -11.6114) -> (-17.7205, -11.2214)
  line L361 (-17.7205, -11.2214) -> (-18.1727, -10.8923)
  line L362 (-18.1727, -10.8923) -> (-18.7112, -10.5998)
  line L363 (-18.7112, -10.5998) -> (-19.2964, -10.3142)
  line L364 (-19.2964, -10.3142) -> (-19.8787, -10.0061)
  line L365 (-19.8787, -10.0061) -> (-20.4057, -9.6512)
  line L366 (-20.4057, -9.6512) -> (-20.8306, -9.2336)
  line L367 (-20.8306, -9.2336) -> (-21.1199, -8.7481)
  line L368 (-21.1199, -8.7481) -> (-21.2586, -8.2004)
  line L369 (-21.2586, -8.2004) -> (-21.2534, -7.6046)
  line L370 (-21.2534, -7.6046) -> (-21.1318, -6.981)
  line L371 (-21.1318, -6.981) -> (-20.9379, -6.3514)
  line L372 (-20.9379, -6.3514) -> (-20.726, -5.7356)
  line L373 (-20.726, -5.7356) -> (-20.5521, -5.148)
  line L374 (-20.5521, -5.148) -> (-20.465, -4.5956)
  line L375 (-20.465, -4.5956) -> (-20.4984, -4.0774)
  line L376 (-20.4984, -4.0774) -> (-20.6658, -3.5859)
  line L377 (-20.6658, -3.5859) -> (-20.9577, -3.1088)
  line L378 (-20.9577, -3.1088) -> (-21.3432, -2.6324)
  line L379 (-21.3432, -2.6324) -> (-21.7746, -2.1446)
  line L380 (-21.7746, -2.1446) -> (-22.1947, -1.6372)
  line L381 (-22.1947, -1.6372) -> (-22.5458, -1.1076)
  line L382 (-22.5458, -1.1076) -> (-22.7785, -0.5592)
  line L383 (-22.7785, -0.5592) -> (-22.86, 0)
  line L384 (-22.86, 0) -> (-22.7785, 0.5592)
  line L385 (-22.7785, 0.5592) -> (-22.5458, 1.1076)
  line L386 (-22.5458, 1.1076) -> (-22.1947, 1.6372)
  line L387 (-22.1947, 1.6372) -> (-21.7746, 2.1446)
  line L388 (-21.7746, 2.1446) -> (-21.3432, 2.6324)
  line L389 (-21.3432, 2.6324) -> (-20.9577, 3.1088)
  line L390 (-20.9577, 3.1088) -> (-20.6658, 3.5859)
  line L391 (-20.6658, 3.5859) -> (-20.4984, 4.0774)
  line L392 (-20.4984, 4.0774) -> (-20.465, 4.5956)
  line L393 (-20.465, 4.5956) -> (-20.5521, 5.148)
  line L394 (-20.5521, 5.148) -> (-20.726, 5.7356)
  line L395 (-20.726, 5.7356) -> (-20.9379, 6.3514)
  line L396 (-20.9379, 6.3514) -> (-21.1318, 6.981)
  line L397 (-21.1318, 6.981) -> (-21.2534, 7.6046)
  line L398 (-21.2534, 7.6046) -> (-21.2586, 8.2004)
  line L399 (-21.2586, 8.2004) -> (-21.1199, 8.7481)
  line L400 (-21.1199, 8.7481) -> (-20.8306, 9.2336)
  line L401 (-20.8306, 9.2336) -> (-20.4057, 9.6512)
  line L402 (-20.4057, 9.6512) -> (-19.8787, 10.0061)
  line L403 (-19.8787, 10.0061) -> (-19.2964, 10.3142)
  line L404 (-19.2964, 10.3142) -> (-18.7112, 10.5998)
  line L405 (-18.7112, 10.5998) -> (-18.1727, 10.8923)
  line L406 (-18.1727, 10.8923) -> (-17.7205, 11.2214)
  line L407 (-17.7205, 11.2214) -> (-17.3777, 11.6114)
  line L408 (-17.3777, 11.6114) -> (-17.1485, 12.0773)
  line L409 (-17.1485, 12.0773) -> (-17.0176, 12.6211)
  line L410 (-17.0176, 12.6211) -> (-16.9534, 13.2305)
  line L411 (-16.9534, 13.2305) -> (-16.9135, 13.8805)
  line L412 (-16.9135, 13.8805) -> (-16.8517, 14.5364)
  line L413 (-16.8517, 14.5364) -> (-16.7255, 15.1591)
  line L414 (-16.7255, 15.1591) -> (-16.5023, 15.7115)
  line L415 (-16.5023, 15.7115) -> (-16.1645, 16.1645)
  line L416 (-16.1645, 16.1645) -> (-15.7115, 16.5023)
  line L417 (-15.7115, 16.5023) -> (-15.1591, 16.7255)
  line L418 (-15.1591, 16.7255) -> (-14.5364, 16.8517)
  line L419 (-14.5364, 16.8517) -> (-13.8805, 16.9135)
  line L420 (-13.8805, 16.9135) -> (-13.2305, 16.9534)
  line L421 (-13.2305, 16.9534) -> (-12.6211, 17.0176)
  line L422 (-12.6211, 17.0176) -> (-12.0773, 17.1485)
  line L423 (-12.0773, 17.1485) -> (-11.6114, 17.3777)
  line L424 (-11.6114, 17.3777) -> (-11.2214, 17.7205)
  line L425 (-11.2214, 17.7205) -> (-10.8923, 18.1727)
  line L426 (-10.8923, 18.1727) -> (-10.5998, 18.7112)
  line L427 (-10.5998, 18.7112) -> (-10.3142, 19.2964)
  line L428 (-10.3142, 19.2964) -> (-10.0061, 19.8787)
  line L429 (-10.0061, 19.8787) -> (-9.6512, 20.4057)
  line L430 (-9.6512, 20.4057) -> (-9.2336, 20.8306)
  line L431 (-9.2336, 20.8306) -> (-8.7481, 21.1199)
  line L432 (-8.7481, 21.1199) -> (-8.2004, 21.2586)
  line L433 (-8.2004, 21.2586) -> (-7.6046, 21.2534)
  line L434 (-7.6046, 21.2534) -> (-6.981, 21.1318)
  line L435 (-6.981, 21.1318) -> (-6.3514, 20.9379)
  line L436 (-6.3514, 20.9379) -> (-5.7356, 20.726)
  line L437 (-5.7356, 20.726) -> (-5.148, 20.5521)
  line L438 (-5.148, 20.5521) -> (-4.5956, 20.465)
  line L439 (-4.5956, 20.465) -> (-4.0774, 20.4984)
  line L440 (-4.0774, 20.4984) -> (-3.5859, 20.6658)
  line L441 (-3.5859, 20.6658) -> (-3.1088, 20.9577)
  line L442 (-3.1088, 20.9577) -> (-2.6324, 21.3432)
  line L443 (-2.6324, 21.3432) -> (-2.1446, 21.7746)
  line L444 (-2.1446, 21.7746) -> (-1.6372, 22.1947)
  line L445 (-1.6372, 22.1947) -> (-1.1076, 22.5458)
  line L446 (-1.1076, 22.5458) -> (-0.5592, 22.7785)
  line L447 (-0.5592, 22.7785) -> (0, 22.86)
  line L448 (0, 22.86) -> (0.5592, 22.7785)
  line L449 (0.5592, 22.7785) -> (1.1076, 22.5458)
  line L450 (1.1076, 22.5458) -> (1.6372, 22.1947)
  line L451 (1.6372, 22.1947) -> (2.1446, 21.7746)
  line L452 (2.1446, 21.7746) -> (2.6324, 21.3432)
  line L453 (2.6324, 21.3432) -> (3.1088, 20.9577)
  line L454 (3.1088, 20.9577) -> (3.5859, 20.6658)
  line L455 (3.5859, 20.6658) -> (4.0774, 20.4984)
  line L456 (4.0774, 20.4984) -> (4.5956, 20.465)
  line L457 (4.5956, 20.465) -> (5.148, 20.5521)
  line L458 (5.148, 20.5521) -> (5.7356, 20.726)
  line L459 (5.7356, 20.726) -> (6.3514, 20.9379)
  line L460 (6.3514, 20.9379) -> (6.981, 21.1318)
  line L461 (6.981, 21.1318) -> (7.6046, 21.2534)
  line L462 (7.6046, 21.2534) -> (8.2004, 21.2586)
  line L463 (8.2004, 21.2586) -> (8.7481, 21.1199)
  line L464 (8.7481, 21.1199) -> (9.2336, 20.8306)
  line L465 (9.2336, 20.8306) -> (9.6512, 20.4057)
  line L466 (9.6512, 20.4057) -> (10.0061, 19.8787)
  line L467 (10.0061, 19.8787) -> (10.3142, 19.2964)
  line L468 (10.3142, 19.2964) -> (10.5998, 18.7112)
  line L469 (10.5998, 18.7112) -> (10.8923, 18.1727)
  line L470 (10.8923, 18.1727) -> (11.2214, 17.7205)
  line L471 (11.2214, 17.7205) -> (11.6114, 17.3777)
  line L472 (11.6114, 17.3777) -> (12.0773, 17.1485)
  line L473 (12.0773, 17.1485) -> (12.6211, 17.0176)
  line L474 (12.6211, 17.0176) -> (13.2305, 16.9534)
  line L475 (13.2305, 16.9534) -> (13.8805, 16.9135)
  line L476 (13.8805, 16.9135) -> (14.5364, 16.8517)
  line L477 (14.5364, 16.8517) -> (15.1591, 16.7255)
  line L478 (15.1591, 16.7255) -> (15.7115, 16.5023)
  line L479 (15.7115, 16.5023) -> (16.1645, 16.1645)
  line L480 (16.1645, 16.1645) -> (16.5023, 15.7115)
  line L481 (16.5023, 15.7115) -> (16.7255, 15.1591)
  line L482 (16.7255, 15.1591) -> (16.8517, 14.5364)
  line L483 (16.8517, 14.5364) -> (16.9135, 13.8805)
  line L484 (16.9135, 13.8805) -> (16.9534, 13.2305)
  line L485 (16.9534, 13.2305) -> (17.0176, 12.6211)
  line L486 (17.0176, 12.6211) -> (17.1485, 12.0773)
  line L487 (17.1485, 12.0773) -> (17.3777, 11.6114)
  line L488 (17.3777, 11.6114) -> (17.7205, 11.2214)
  line L489 (17.7205, 11.2214) -> (18.1727, 10.8923)
  line L490 (18.1727, 10.8923) -> (18.7112, 10.5998)
  line L491 (18.7112, 10.5998) -> (19.2964, 10.3142)
  line L492 (19.2964, 10.3142) -> (19.8787, 10.0061)
  line L493 (19.8787, 10.0061) -> (20.4057, 9.6512)
  line L494 (20.4057, 9.6512) -> (20.8306, 9.2336)
  line L495 (20.8306, 9.2336) -> (21.1199, 8.7481)
  line L496 (21.1199, 8.7481) -> (21.2586, 8.2004)
  line L497 (21.2586, 8.2004) -> (21.2534, 7.6046)
  line L498 (21.2534, 7.6046) -> (21.1318, 6.981)
  line L499 (21.1318, 6.981) -> (20.9379, 6.3514)
  line L500 (20.9379, 6.3514) -> (20.726, 5.7356)
  line L501 (20.726, 5.7356) -> (20.5521, 5.148)
  line L502 (20.5521, 5.148) -> (20.465, 4.5956)
  line L503 (20.465, 4.5956) -> (20.4984, 4.0774)
  line L504 (20.4984, 4.0774) -> (20.6658, 3.5859)
  line L505 (20.6658, 3.5859) -> (20.9577, 3.1088)
  line L506 (20.9577, 3.1088) -> (21.3432, 2.6324)
  line L507 (21.3432, 2.6324) -> (21.7746, 2.1446)
  line L508 (21.7746, 2.1446) -> (22.1947, 1.6372)
  line L509 (22.1947, 1.6372) -> (22.5458, 1.1076)
  line L510 (22.5458, 1.1076) -> (22.7785, 0.5592)
  line L511 (22.7785, 0.5592) -> (22.86, 0)
extrude "涟漪_004 (1)" add sketch "草图5" along normal blind 1.63 bodies 1 in component "01_月饼_金_68mm"
sketch "草图6" plane through (0, 0, 25.97) normal (0, 0, 1) x (1, 0, 0) in component "01_月饼_金_68mm"
  line L0 (-6.9964, -7.7969) -> (7.1229, -7.7561)
  line L1 (7.1229, -7.7561) -> (7.4326, -7.6882)
  line L2 (7.4326, -7.6882) -> (7.4922, -7.5794)
  line L3 (7.4922, -7.5794) -> (7.2448, -7.1444)
  line L4 (7.2448, -7.1444) -> (5.9266, -5.7943)
  line L5 (5.9266, -5.7943) -> (5.6004, -5.8104)
  line L6 (5.6004, -5.8104) -> (4.5128, -7.0841)
  line L7 (4.5128, -7.0841) -> (2.2291, -7.0743)
  line L8 (2.2291, -7.0743) -> (4.0779, -4.8219)
  line L9 (4.0779, -4.8219) -> (4.8831, -4.4257)
  line L10 (4.8831, -4.4257) -> (4.8782, -4.2082)
  line L11 (4.8782, -4.2082) -> (4.6217, -3.9513)
  line L12 (4.6217, -3.9513) -> (3.0992, -3.0665)
  line L13 (3.0992, -3.0665) -> (2.9622, -3.1207)
  line L14 (2.9622, -3.1207) -> (2.144, -5.2957)
  line L15 (2.144, -5.2957) -> (1.2503, -7.0319)
  line L16 (1.2503, -7.0319) -> (1.1416, -7.1047)
  line L17 (1.1416, -7.1047) -> (0.5488, -7.0357)
  line L18 (0.5488, -7.0357) -> (0.5978, -2.5488)
  line L19 (0.5978, -2.5488) -> (6.0353, -2.5396)
  line L20 (6.0353, -2.5396) -> (6.2528, -2.5175)
  line L21 (6.2528, -2.5175) -> (6.3447, -2.3594)
  line L22 (6.3447, -2.3594) -> (6.2626, -2.1419)
  line L23 (6.2626, -2.1419) -> (5.8179, -1.6727)
  line L24 (5.8179, -1.6727) -> (4.9479, -0.9294)
  line L25 (4.9479, -0.9294) -> (4.6217, -0.7662)
  line L26 (4.6217, -0.7662) -> (4.2954, -0.8934)
  line L27 (4.2954, -0.8934) -> (3.4254, -1.9724)
  line L28 (3.4254, -1.9724) -> (0.5564, -1.9244)
  line L29 (0.5564, -1.9244) -> (0.5692, 0.5768)
  line L30 (0.5692, 0.5768) -> (4.4041, 0.6711)
  line L31 (4.4041, 0.6711) -> (4.3447, 0.9031)
  line L32 (4.3447, 0.9031) -> (3.4254, 1.7351)
  line L33 (3.4254, 1.7351) -> (2.6641, 2.1849)
  line L34 (2.6641, 2.1849) -> (2.4466, 2.1387)
  line L35 (2.4466, 2.1387) -> (1.6853, 1.2503)
  line L36 (1.6853, 1.2503) -> (-3.8608, 1.245)
  line L37 (-3.8608, 1.245) -> (-4.235, 1.3381)
  line L38 (-4.235, 1.3381) -> (-3.3171, 2.0668)
  line L39 (-3.3171, 2.0668) -> (-2.0719, 3.2956)
  line L40 (-2.0719, 3.2956) -> (0.0074, 5.9056)
  line L41 (0.0074, 5.9056) -> (0.1628, 5.9808)
  line L42 (0.1628, 5.9808) -> (0.7726, 4.8181)
  line L43 (0.7726, 4.8181) -> (1.4406, 3.8393)
  line L44 (1.4406, 3.8393) -> (3.0657, 2.0993)
  line L45 (3.0657, 2.0993) -> (3.8603, 1.376)
  line L46 (3.8603, 1.376) -> (6.0353, 0.1076)
  line L47 (6.0353, 0.1076) -> (6.3617, 0.0877)
  line L48 (6.3617, 0.0877) -> (7.1229, 0.8094)
  line L49 (7.1229, 0.8094) -> (8.3699, 1.1206)
  line L50 (8.3699, 1.1206) -> (8.3192, 1.4998)
  line L51 (8.3192, 1.4998) -> (5.9266, 2.1644)
  line L52 (5.9266, 2.1644) -> (3.7517, 3.2684)
  line L53 (3.7517, 3.2684) -> (2.0116, 4.6652)
  line L54 (2.0116, 4.6652) -> (0.6879, 6.2318)
  line L55 (0.6879, 6.2318) -> (0.545, 6.4493)
  line L56 (0.545, 6.4493) -> (0.9439, 6.6668)
  line L57 (0.9439, 6.6668) -> (1.0645, 6.8843)
  line L58 (1.0645, 6.8843) -> (0.9904, 6.9931)
  line L59 (0.9904, 6.9931) -> (0.3803, 7.3551)
  line L60 (0.3803, 7.3551) -> (-1.0334, 7.797)
  line L61 (-1.0334, 7.797) -> (-2.4172, 5.2531)
  line L62 (-2.4172, 5.2531) -> (-3.9255, 3.1868)
  line L63 (-3.9255, 3.1868) -> (-6.0358, 1.1825)
  line L64 (-6.0358, 1.1825) -> (-8.3698, -0.5107)
  line L65 (-8.3698, -0.5107) -> (-8.1022, -0.9733)
  line L66 (-8.1022, -0.9733) -> (-6.2533, -0.0157)
  line L67 (-6.2533, -0.0157) -> (-4.7308, 0.9523)
  line L68 (-4.7308, 0.9523) -> (-4.5133, 0.5243)
  line L69 (-4.5133, 0.5243) -> (-3.6433, 0.6134)
  line L70 (-3.6433, 0.6134) -> (-1.1854, 0.5768)
  line L71 (-1.1854, 0.5768) -> (-1.1512, -1.8157)
  line L72 (-1.1512, -1.8157) -> (-1.2509, -1.9724)
  line L73 (-1.2509, -1.9724) -> (-6.6179, -1.9244)
  line L74 (-6.6179, -1.9244) -> (-6.2533, -2.6658)
  line L75 (-6.2533, -2.6658) -> (-5.4922, -2.5412)
  line L76 (-5.4922, -2.5412) -> (-1.186, -2.5769)
  line L77 (-1.186, -2.5769) -> (-1.1512, -7.0357)
  line L78 (-1.1512, -7.0357) -> (-1.2509, -7.1047)
  line L79 (-1.2509, -7.1047) -> (-3.4259, -7.0743)
  line L80 (-3.4259, -7.0743) -> (-2.9574, -6.6007)
  line L81 (-2.9574, -6.6007) -> (-2.6385, -5.9482)
  line L82 (-2.6385, -5.9482) -> (-2.6207, -5.2957)
  line L83 (-2.6207, -5.2957) -> (-2.7518, -4.9694)
  line L84 (-2.7518, -4.9694) -> (-3.1179, -4.5344)
  line L85 (-3.1179, -4.5344) -> (-3.8608, -3.9534)
  line L86 (-3.8608, -3.9534) -> (-5.0571, -3.2961)
  line L87 (-5.0571, -3.2961) -> (-5.2746, -3.2675)
  line L88 (-5.2746, -3.2675) -> (-5.4274, -3.4469)
  line L89 (-5.4274, -3.4469) -> (-5.4213, -3.6644)
  line L90 (-5.4213, -3.6644) -> (-4.5784, -5.187)
  line L91 (-4.5784, -5.187) -> (-4.2244, -6.6007)
  line L92 (-4.2244, -6.6007) -> (-3.99, -7.0357)
  line L93 (-3.99, -7.0357) -> (-4.0783, -7.1047)
  line L94 (-4.0783, -7.1047) -> (-7.6671, -7.0488)
  line L95 (-7.6671, -7.0488) -> (-7.7153, -7.2532)
  line L96 (-7.7153, -7.2532) -> (-7.4923, -7.7969)
  line L97 (-7.4923, -7.7969) -> (-6.9964, -7.7969)
extrude "文字_005 (1)" add sketch "草图6" along normal blind 1.63 bodies 1 in component "01_月饼_金_68mm"
sketch "草图1 (2)" plane through (0, 0, 0) normal (0, 0, 1) x (1, 0, 0) in component "02_模具外套筒"
  circle A0 centre (0, 0) radius 37.5
extrude "套筒外壁 (1)" add sketch "草图1 (2)" along normal blind 50 separate body makes body 2 in component "02_模具外套筒"
ref_plane "工作平面1" through (0, 0, -0.03) normal (0, 0, 1) x (1, 0, 0) in component "02_模具外套筒"